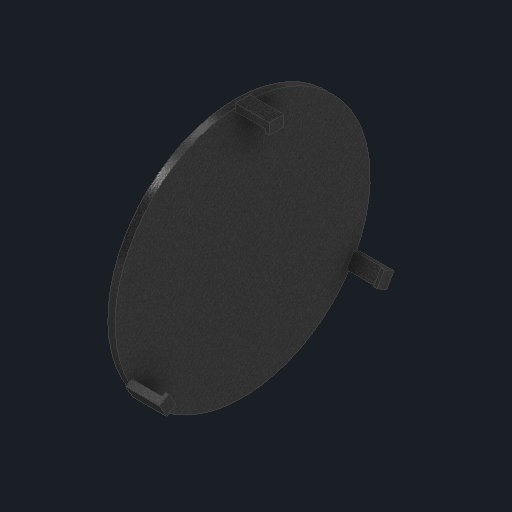
# Autodesk Inventor part: c8n_mirror_support
Saved by Autodesk Inventor 2027.1 (Build 311270010, 270A)
## iProperties
Created: 2026-11-04
Part Number: c8n_mirror_support
Material: Generic
Description: Primary mirror support plate with 3 mirror clips
Document SubType Name: Modeling
Designer: Claude (from photos)
Density: 1 g/cm^3
Appearance: Black Cast
Author: alexg
Autodesk Inventor part; units mm, degrees
ref_plane "Work Plane1" through (12, 0, 0) normal (1, 0, 0) x (0, 1, 0)
sketch "Mirror support plate sketch" plane through (12, 0, 0) normal (1, 0, 0) x (0, 1, 0)
  circle A0 centre (0, 0) radius 105
  constraints: 1 centre point
extrude "Mirror support plate" add sketch "Mirror support plate sketch" along normal blind 6
ref_plane "Work Plane2" through (18, 0, 0) normal (1, 0, 0) x (0, 1, 0)
sketch "Clip legs sketch" plane through (18, 0, 0) normal (1, 0, 0) x (0, 1, 0)
  line L0 (102, -6) -> (108, -6)
  line L1 (108, -6) -> (108, 6)
  line L2 (108, 6) -> (102, 6)
  line L3 (102, 6) -> (102, -6)
  line L4 (-45.8038, 91.3346) -> (-48.8038, 96.5307)
  line L5 (-48.8038, 96.5307) -> (-59.1962, 90.5307)
  line L6 (-59.1962, 90.5307) -> (-56.1962, 85.3346)
  line L7 (-56.1962, 85.3346) -> (-45.8038, 91.3346)
  line L8 (-56.1962, -85.3346) -> (-59.1962, -90.5307)
  line L9 (-59.1962, -90.5307) -> (-48.8038, -96.5307)
  line L10 (-48.8038, -96.5307) -> (-45.8038, -91.3346)
  line L11 (-45.8038, -91.3346) -> (-56.1962, -85.3346)
  constraints: 24 end point
extrude "Clip legs" add sketch "Clip legs sketch" along normal blind 28
ref_plane "Work Plane3" through (43, 0, 0) normal (1, 0, 0) x (0, 1, 0)
sketch "Clip lips sketch" plane through (43, 0, 0) normal (1, 0, 0) x (0, 1, 0)
  line L0 (99, -6) -> (102, -6)
  line L1 (102, -6) -> (102, 6)
  line L2 (102, 6) -> (99, 6)
  line L3 (99, 6) -> (99, -6)
  line L4 (-44.3038, 88.7365) -> (-45.8038, 91.3346)
  line L5 (-45.8038, 91.3346) -> (-56.1962, 85.3346)
  line L6 (-56.1962, 85.3346) -> (-54.6962, 82.7365)
  line L7 (-54.6962, 82.7365) -> (-44.3038, 88.7365)
  line L8 (-54.6962, -82.7365) -> (-56.1962, -85.3346)
  line L9 (-56.1962, -85.3346) -> (-45.8038, -91.3346)
  line L10 (-45.8038, -91.3346) -> (-44.3038, -88.7365)
  line L11 (-44.3038, -88.7365) -> (-54.6962, -82.7365)
  constraints: 24 end point
extrude "Clip lips" add sketch "Clip lips sketch" along normal blind 3
body "Solid1"
